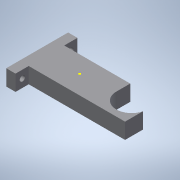
# Autodesk Inventor part: Csőtartó
Saved by Autodesk Inventor 2020 (Build 240168000, 168)
## iProperties
Created: 2024-06-15
Part Number: Csőtartó
Material: Generic
Document SubType Name: Modeling
Designer: CAD
Density: 1 g/cm^3
Appearance: Default
Author: CAD
Autodesk Inventor part; units mm, degrees
ref_plane "YZ Plane" through (0, 0, 0) normal (1, 0, 0) x (0, 1, 0)
ref_plane "XZ Plane" through (0, 0, 0) normal (0, 1, 0) x (-1, 0, 0)
ref_plane "XY Plane" through (0, 0, 0) normal (0, 0, 1) x (1, 0, 0)
sketch "Sketch1" plane through (0, 0, 0) normal (0, 0, 1) x (1, 0, 0)
  line L0 (-31.792, 23.1285) -> (-24.718, 23.1285)
  line L1 (-24.7071, -23.8715) -> (-31.792, -23.8715)
  line L2 (-31.792, -23.8715) -> (-31.792, 23.1285)
  arc A0 (25.3403, 3.15) -> (48.3913, -0.2228) centre (37.0187, 2.5089) ccw
  line L3 (25.3403, 13.1285) -> (25.3403, 3.15)
  line L4 (48.3913, -0.2228) -> (48.3913, -13.8715)
  line L5 (48.3913, -13.8715) -> (-24.7071, -13.8715)
  line L6 (-24.7071, -13.8715) -> (-24.7071, -23.8715)
  line L7 (25.3403, 13.1285) -> (-24.718, 13.1285)
  line L8 (-24.718, 13.1285) -> (-24.718, 23.1285)
  point P0 (0, 0)
  dimension "d3" = 47
  dimension "d5" = 10
  dimension "d6" = 10
  dimension "d35" = 73.0984
  dimension "d36" = 7.074
  constraints: 18 end point, 4 perpendicular, 3 horizontal, 3 parallel, 2 point on circle, 1 centre point
  measures "d3" distance of L0.start L1.end
  measures "d5" distance of L1.start L5.end
  measures "d6" distance of L0.end L7.end
  measures "d35" distance of L5.end L4.end
  measures "d36" distance of L0.end L0.start
extrude "Extrusion1" add sketch "Sketch1" along normal blind 12
sketch "Sketch2" plane through (0, 0, 12) normal (0, 0, 1) x (1, 0, 0)
  point P0 (0, 0)
sketch "Sketch5" plane through (-24.718, 13.1285, 0) normal (1, 0, 0) x (0, 0, -1)
  circle A0 centre (-6, 5) radius 2
  point P0 (0, -13.1285)
  point P1 (-12, 10)
  point P2 (0, 0)
  point P3 (-12, 0)
  point P4 (0, 10)
  dimension "d25" = 4
  constraints: 1 centre point
  measures "d25" diameter of A0
extrude "Extrusion3" cut sketch "Sketch5" against normal blind 9
sketch "Sketch7" plane through (-24.7071, -23.8715, 0) normal (1, 0, 0) x (0, 0, -1)
  circle A0 centre (-6.1942, 5.2063) radius 2
  point P0 (0, 23.8715)
  dimension "d32" = 4
  constraints: 1 centre point
  measures "d32" diameter of A0
extrude "Extrusion5" cut sketch "Sketch7" against normal blind 8.25
body "Solid1"
